Autodesk Fusion 360 part; units mm, degrees
(part 3 of 3)
sketch "스케치4" plane through (0, 0, 0) normal (0, -1, 0) x (1, 0, 0)
  circle A0 centre (-215, 0) radius 2.05
  circle A1 centre (-155, -60) radius 2.05
  circle A2 centre (-155, 60) radius 2.05
  circle A3 centre (-95, 0) radius 2.05
  circle A4 centre (-155, 0) radius 2.05
  line L0 (-89.3831, 6.1447) -> (-93.6198, 5.748)
  arc A5 (-94.0551, 6.1063) -> (-93.6198, 5.748) centre (-93.6571, 6.1462) ccw
  arc A6 (-94.0551, 6.1063) -> (-95.151, 13.0255) centre (-155, 0) ccw
  arc A7 (-94.8478, 13.5009) -> (-95.151, 13.0255) centre (-94.7602, 13.1106) ccw
  line L1 (-94.8478, 13.5009) -> (-90.6958, 14.4328)
  spline S0 degree 3 poles (-87.963, 15.6993) (-89.4342, 14.8406) (-90.378, 14.5249) (-90.6958, 14.4328) knots 0 0 0 0 1 1 1 1
  spline S1 degree 3 poles (-81.0471, 21.4743) (-83.7822, 18.497) (-86.2119, 16.7247) (-87.963, 15.6993) knots 0 0 0 0 1 1 1 1
  arc A8 (-81.0471, 21.4743) -> (-82.5485, 26.0954) centre (-155, 0) ccw
  spline S2 degree 3 poles (-91.5382, 26.7024) (-89.5187, 26.9021) (-86.5113, 26.8963) (-82.5485, 26.0954) knots 0 0 0 0 1 1 1 1
  spline S3 degree 3 poles (-94.4934, 26.1207) (-94.1822, 26.2329) (-93.2331, 26.5323) (-91.5382, 26.7024) knots 0 0 0 0 1 1 1 1
  line L2 (-94.4934, 26.1207) -> (-98.4002, 24.4342)
  arc A9 (-98.925, 24.6405) -> (-98.4002, 24.4342) centre (-98.5588, 24.8014) ccw
  arc A10 (-98.925, 24.6405) -> (-102.1054, 30.8824) centre (-155, 0) ccw
  arc A11 (-101.9638, 31.4282) -> (-102.1054, 30.8824) centre (-101.7599, 31.084) ccw
  line L3 (-101.9638, 31.4282) -> (-98.303, 33.5975)
  spline S4 degree 3 poles (-96.0954, 35.6464) (-97.2292, 34.3752) (-98.0293, 33.7833) (-98.303, 33.5975) knots 0 0 0 0 1 1 1 1
  spline S5 degree 3 poles (-91.3025, 43.276) (-92.9838, 39.5992) (-94.7468, 37.1628) (-96.0954, 35.6464) knots 0 0 0 0 1 1 1 1
  arc A12 (-91.3025, 43.276) -> (-94.1585, 47.2069) centre (-155, 0) ccw
  spline S6 degree 3 poles (-102.8957, 45.0063) (-101.0368, 45.8202) (-98.1748, 46.7441) (-94.1585, 47.2069) knots 0 0 0 0 1 1 1 1
  spline S7 degree 3 poles (-105.5266, 43.5398) (-105.2653, 43.7427) (-104.4551, 44.3208) (-102.8957, 45.0063) knots 0 0 0 0 1 1 1 1
  line L4 (-105.5266, 43.5398) -> (-108.721, 40.7286)
  arc A13 (-109.2838, 40.7626) -> (-108.721, 40.7286) centre (-108.9852, 41.0288) ccw
  arc A14 (-109.2838, 40.7626) -> (-114.2374, 45.7162) centre (-155, 0) ccw
  arc A15 (-114.2714, 46.279) -> (-114.2374, 45.7162) centre (-113.9712, 46.0148) ccw
  line L5 (-114.2714, 46.279) -> (-111.4602, 49.4734)
  spline S8 degree 3 poles (-109.9937, 52.1043) (-110.6792, 50.5449) (-111.2573, 49.7347) (-111.4602, 49.4734) knots 0 0 0 0 1 1 1 1
  spline S9 degree 3 poles (-107.7931, 60.8415) (-108.2559, 56.8252) (-109.1798, 53.9632) (-109.9937, 52.1043) knots 0 0 0 0 1 1 1 1
  arc A16 (-107.7931, 60.8415) -> (-111.724, 63.6975) centre (-155, 0) ccw
  spline S10 degree 3 poles (-119.3536, 58.9046) (-117.8372, 60.2532) (-115.4008, 62.0162) (-111.724, 63.6975) knots 0 0 0 0 1 1 1 1
  spline S11 degree 3 poles (-121.4025, 56.697) (-121.2167, 56.9707) (-120.6248, 57.7708) (-119.3536, 58.9046) knots 0 0 0 0 1 1 1 1
  line L6 (-121.4025, 56.697) -> (-123.5718, 53.0362)
  arc A17 (-124.1176, 52.8946) -> (-123.5718, 53.0362) centre (-123.916, 53.2401) ccw
  arc A18 (-124.1176, 52.8946) -> (-130.3595, 56.075) centre (-155, 0) ccw
  arc A19 (-130.5658, 56.5998) -> (-130.3595, 56.075) centre (-130.1986, 56.4412) ccw
  line L7 (-130.5658, 56.5998) -> (-128.8793, 60.5066)
  spline S12 degree 3 poles (-128.2976, 63.4618) (-128.4677, 61.7669) (-128.7671, 60.8178) (-128.8793, 60.5066) knots 0 0 0 0 1 1 1 1
  spline S13 degree 3 poles (-128.9046, 72.4515) (-128.1037, 68.4887) (-128.0979, 65.4813) (-128.2976, 63.4618) knots 0 0 0 0 1 1 1 1
  arc A20 (-128.9046, 72.4515) -> (-133.5257, 73.9529) centre (-155, 0) ccw
  spline S14 degree 3 poles (-139.3007, 67.037) (-138.2753, 68.7881) (-136.503, 71.2178) (-133.5257, 73.9529) knots 0 0 0 0 1 1 1 1
  spline S15 degree 3 poles (-140.5672, 64.3042) (-140.4751, 64.622) (-140.1594, 65.5658) (-139.3007, 67.037) knots 0 0 0 0 1 1 1 1
  line L8 (-140.5672, 64.3042) -> (-141.4991, 60.1522)
  arc A21 (-141.9745, 59.849) -> (-141.4991, 60.1522) centre (-141.8894, 60.2398) ccw
  arc A22 (-141.9745, 59.849) -> (-148.8937, 60.9449) centre (-155, 0) ccw
  arc A23 (-149.252, 61.3802) -> (-148.8937, 60.9449) centre (-148.8538, 61.3429) ccw
  line L9 (-149.252, 61.3802) -> (-148.8553, 65.6169)
  spline S16 degree 3 poles (-149.2153, 68.6073) (-148.8533, 66.9428) (-148.8447, 65.9476) (-148.8553, 65.6169) knots 0 0 0 0 1 1 1 1
  spline S17 degree 3 poles (-152.5706, 76.9693) (-150.5842, 73.448) (-149.6495, 70.5896) (-149.2153, 68.6073) knots 0 0 0 0 1 1 1 1
  arc A24 (-152.5706, 76.9693) -> (-157.4294, 76.9693) centre (-155, 0) ccw
  spline S18 degree 3 poles (-160.7847, 68.6073) (-160.3505, 70.5896) (-159.4158, 73.448) (-157.4294, 76.9693) knots 0 0 0 0 1 1 1 1
  spline S19 degree 3 poles (-161.1447, 65.6169) (-161.1553, 65.9476) (-161.1467, 66.9428) (-160.7847, 68.6073) knots 0 0 0 0 1 1 1 1
  line L10 (-161.1447, 65.6169) -> (-160.748, 61.3802)
  arc A25 (-161.1063, 60.9449) -> (-160.748, 61.3802) centre (-161.1462, 61.3429) ccw
  arc A26 (-161.1063, 60.9449) -> (-168.0255, 59.849) centre (-155, 0) ccw
  arc A27 (-168.5009, 60.1522) -> (-168.0255, 59.849) centre (-168.1106, 60.2398) ccw
  line L11 (-168.5009, 60.1522) -> (-169.4328, 64.3042)
  spline S20 degree 3 poles (-170.6993, 67.037) (-169.8406, 65.5658) (-169.5249, 64.622) (-169.4328, 64.3042) knots 0 0 0 0 1 1 1 1
  spline S21 degree 3 poles (-176.4743, 73.9529) (-173.497, 71.2178) (-171.7247, 68.7881) (-170.6993, 67.037) knots 0 0 0 0 1 1 1 1
  arc A28 (-176.4743, 73.9529) -> (-181.0954, 72.4515) centre (-155, 0) ccw
  spline S22 degree 3 poles (-181.7024, 63.4618) (-181.9021, 65.4813) (-181.8963, 68.4887) (-181.0954, 72.4515) knots 0 0 0 0 1 1 1 1
  spline S23 degree 3 poles (-181.1207, 60.5066) (-181.2329, 60.8178) (-181.5323, 61.7669) (-181.7024, 63.4618) knots 0 0 0 0 1 1 1 1
  line L12 (-181.1207, 60.5066) -> (-179.4342, 56.5998)
  arc A29 (-179.6405, 56.075) -> (-179.4342, 56.5998) centre (-179.8014, 56.4412) ccw
  arc A30 (-179.6405, 56.075) -> (-185.8824, 52.8946) centre (-155, 0) ccw
  arc A31 (-186.4282, 53.0362) -> (-185.8824, 52.8946) centre (-186.084, 53.2401) ccw
  line L13 (-186.4282, 53.0362) -> (-188.5975, 56.697)
  spline S24 degree 3 poles (-190.6464, 58.9046) (-189.3752, 57.7708) (-188.7833, 56.9707) (-188.5975, 56.697) knots 0 0 0 0 1 1 1 1
  spline S25 degree 3 poles (-198.276, 63.6975) (-194.5992, 62.0162) (-192.1628, 60.2532) (-190.6464, 58.9046) knots 0 0 0 0 1 1 1 1
  arc A32 (-198.276, 63.6975) -> (-202.2069, 60.8415) centre (-155, 0) ccw
  spline S26 degree 3 poles (-200.0063, 52.1043) (-200.8202, 53.9632) (-201.7441, 56.8252) (-202.2069, 60.8415) knots 0 0 0 0 1 1 1 1
  spline S27 degree 3 poles (-198.5398, 49.4734) (-198.7427, 49.7347) (-199.3208, 50.5449) (-200.0063, 52.1043) knots 0 0 0 0 1 1 1 1
  line L14 (-198.5398, 49.4734) -> (-195.7286, 46.279)
  arc A33 (-195.7626, 45.7162) -> (-195.7286, 46.279) centre (-196.0288, 46.0148) ccw
  arc A34 (-195.7626, 45.7162) -> (-200.7162, 40.7626) centre (-155, 0) ccw
  arc A35 (-201.279, 40.7286) -> (-200.7162, 40.7626) centre (-201.0148, 41.0288) ccw
  line L15 (-201.279, 40.7286) -> (-204.4734, 43.5398)
  spline S28 degree 3 poles (-207.1043, 45.0063) (-205.5449, 44.3208) (-204.7347, 43.7427) (-204.4734, 43.5398) knots 0 0 0 0 1 1 1 1
  spline S29 degree 3 poles (-215.8415, 47.2069) (-211.8252, 46.7441) (-208.9632, 45.8202) (-207.1043, 45.0063) knots 0 0 0 0 1 1 1 1
  arc A36 (-215.8415, 47.2069) -> (-218.6975, 43.276) centre (-155, 0) ccw
  spline S30 degree 3 poles (-213.9046, 35.6464) (-215.2532, 37.1628) (-217.0162, 39.5992) (-218.6975, 43.276) knots 0 0 0 0 1 1 1 1
  spline S31 degree 3 poles (-211.697, 33.5975) (-211.9707, 33.7833) (-212.7708, 34.3752) (-213.9046, 35.6464) knots 0 0 0 0 1 1 1 1
  line L16 (-211.697, 33.5975) -> (-208.0362, 31.4282)
  arc A37 (-207.8946, 30.8824) -> (-208.0362, 31.4282) centre (-208.2401, 31.084) ccw
  arc A38 (-207.8946, 30.8824) -> (-211.075, 24.6405) centre (-155, 0) ccw
  arc A39 (-211.5998, 24.4342) -> (-211.075, 24.6405) centre (-211.4412, 24.8014) ccw
  line L17 (-211.5998, 24.4342) -> (-215.5066, 26.1207)
  spline S32 degree 3 poles (-218.4618, 26.7024) (-216.7669, 26.5323) (-215.8178, 26.2329) (-215.5066, 26.1207) knots 0 0 0 0 1 1 1 1
  spline S33 degree 3 poles (-227.4515, 26.0954) (-223.4887, 26.8963) (-220.4813, 26.9021) (-218.4618, 26.7024) knots 0 0 0 0 1 1 1 1
  arc A40 (-227.4515, 26.0954) -> (-228.9529, 21.4743) centre (-155, 0) ccw
  spline S34 degree 3 poles (-222.037, 15.6993) (-223.7881, 16.7247) (-226.2178, 18.497) (-228.9529, 21.4743) knots 0 0 0 0 1 1 1 1
  spline S35 degree 3 poles (-219.3042, 14.4328) (-219.622, 14.5249) (-220.5658, 14.8406) (-222.037, 15.6993) knots 0 0 0 0 1 1 1 1
  line L18 (-219.3042, 14.4328) -> (-215.1522, 13.5009)
  arc A41 (-214.849, 13.0255) -> (-215.1522, 13.5009) centre (-215.2398, 13.1106) ccw
  arc A42 (-214.849, 13.0255) -> (-215.9449, 6.1063) centre (-155, 0) ccw
  arc A43 (-216.3802, 5.748) -> (-215.9449, 6.1063) centre (-216.3429, 6.1462) ccw
  line L19 (-216.3802, 5.748) -> (-220.6169, 6.1447)
  spline S36 degree 3 poles (-223.6073, 5.7847) (-221.9428, 6.1467) (-220.9476, 6.1553) (-220.6169, 6.1447) knots 0 0 0 0 1 1 1 1
  spline S37 degree 3 poles (-231.9693, 2.4294) (-228.448, 4.4158) (-225.5896, 5.3505) (-223.6073, 5.7847) knots 0 0 0 0 1 1 1 1
  arc A44 (-231.9693, 2.4294) -> (-231.9693, -2.4294) centre (-155, 0) ccw
  spline S38 degree 3 poles (-223.6073, -5.7847) (-225.5896, -5.3505) (-228.448, -4.4158) (-231.9693, -2.4294) knots 0 0 0 0 1 1 1 1
  spline S39 degree 3 poles (-220.6169, -6.1447) (-220.9476, -6.1553) (-221.9428, -6.1467) (-223.6073, -5.7847) knots 0 0 0 0 1 1 1 1
  line L20 (-220.6169, -6.1447) -> (-216.3802, -5.748)
  arc A45 (-215.9449, -6.1063) -> (-216.3802, -5.748) centre (-216.3429, -6.1462) ccw
  arc A46 (-215.9449, -6.1063) -> (-214.849, -13.0255) centre (-155, 0) ccw
  arc A47 (-215.1522, -13.5009) -> (-214.849, -13.0255) centre (-215.2398, -13.1106) ccw
  line L21 (-215.1522, -13.5009) -> (-219.3042, -14.4328)
  spline S40 degree 3 poles (-222.037, -15.6993) (-220.5658, -14.8406) (-219.622, -14.5249) (-219.3042, -14.4328) knots 0 0 0 0 1 1 1 1
  spline S41 degree 3 poles (-228.9529, -21.4743) (-226.2178, -18.497) (-223.7881, -16.7247) (-222.037, -15.6993) knots 0 0 0 0 1 1 1 1
  arc A48 (-228.9529, -21.4743) -> (-227.4515, -26.0954) centre (-155, 0) ccw
  spline S42 degree 3 poles (-218.4618, -26.7024) (-220.4813, -26.9021) (-223.4887, -26.8963) (-227.4515, -26.0954) knots 0 0 0 0 1 1 1 1
  spline S43 degree 3 poles (-215.5066, -26.1207) (-215.8178, -26.2329) (-216.7669, -26.5323) (-218.4618, -26.7024) knots 0 0 0 0 1 1 1 1
  line L22 (-215.5066, -26.1207) -> (-211.5998, -24.4342)
  arc A49 (-211.075, -24.6405) -> (-211.5998, -24.4342) centre (-211.4412, -24.8014) ccw
  arc A50 (-211.075, -24.6405) -> (-207.8946, -30.8824) centre (-155, 0) ccw
  arc A51 (-208.0362, -31.4282) -> (-207.8946, -30.8824) centre (-208.2401, -31.084) ccw
  line L23 (-208.0362, -31.4282) -> (-211.697, -33.5975)
  spline S44 degree 3 poles (-213.9046, -35.6464) (-212.7708, -34.3752) (-211.9707, -33.7833) (-211.697, -33.5975) knots 0 0 0 0 1 1 1 1
  spline S45 degree 3 poles (-218.6975, -43.276) (-217.0162, -39.5992) (-215.2532, -37.1628) (-213.9046, -35.6464) knots 0 0 0 0 1 1 1 1
  arc A52 (-218.6975, -43.276) -> (-215.8415, -47.2069) centre (-155, 0) ccw
  spline S46 degree 3 poles (-207.1043, -45.0063) (-208.9632, -45.8202) (-211.8252, -46.7441) (-215.8415, -47.2069) knots 0 0 0 0 1 1 1 1
  spline S47 degree 3 poles (-204.4734, -43.5398) (-204.7347, -43.7427) (-205.5449, -44.3208) (-207.1043, -45.0063) knots 0 0 0 0 1 1 1 1
  line L24 (-204.4734, -43.5398) -> (-201.279, -40.7286)
  arc A53 (-200.7162, -40.7626) -> (-201.279, -40.7286) centre (-201.0148, -41.0288) ccw
  arc A54 (-200.7162, -40.7626) -> (-195.7626, -45.7162) centre (-155, 0) ccw
  arc A55 (-195.7286, -46.279) -> (-195.7626, -45.7162) centre (-196.0288, -46.0148) ccw
  line L25 (-195.7286, -46.279) -> (-198.5398, -49.4734)
  spline S48 degree 3 poles (-200.0063, -52.1043) (-199.3208, -50.5449) (-198.7427, -49.7347) (-198.5398, -49.4734) knots 0 0 0 0 1 1 1 1
  spline S49 degree 3 poles (-202.2069, -60.8415) (-201.7441, -56.8252) (-200.8202, -53.9632) (-200.0063, -52.1043) knots 0 0 0 0 1 1 1 1
  arc A56 (-202.2069, -60.8415) -> (-198.276, -63.6975) centre (-155, 0) ccw
  spline S50 degree 3 poles (-190.6464, -58.9046) (-192.1628, -60.2532) (-194.5992, -62.0162) (-198.276, -63.6975) knots 0 0 0 0 1 1 1 1
  spline S51 degree 3 poles (-188.5975, -56.697) (-188.7833, -56.9707) (-189.3752, -57.7708) (-190.6464, -58.9046) knots 0 0 0 0 1 1 1 1
  line L26 (-188.5975, -56.697) -> (-186.4282, -53.0362)
  arc A57 (-185.8824, -52.8946) -> (-186.4282, -53.0362) centre (-186.084, -53.2401) ccw
  arc A58 (-185.8824, -52.8946) -> (-179.6405, -56.075) centre (-155, 0) ccw
  arc A59 (-179.4342, -56.5998) -> (-179.6405, -56.075) centre (-179.8014, -56.4412) ccw
  line L27 (-179.4342, -56.5998) -> (-181.1207, -60.5066)
  spline S52 degree 3 poles (-181.7024, -63.4618) (-181.5323, -61.7669) (-181.2329, -60.8178) (-181.1207, -60.5066) knots 0 0 0 0 1 1 1 1
  spline S53 degree 3 poles (-181.0954, -72.4515) (-181.8963, -68.4887) (-181.9021, -65.4813) (-181.7024, -63.4618) knots 0 0 0 0 1 1 1 1
  arc A60 (-181.0954, -72.4515) -> (-176.4743, -73.9529) centre (-155, 0) ccw
  spline S54 degree 3 poles (-170.6993, -67.037) (-171.7247, -68.7881) (-173.497, -71.2178) (-176.4743, -73.9529) knots 0 0 0 0 1 1 1 1
  spline S55 degree 3 poles (-169.4328, -64.3042) (-169.5249, -64.622) (-169.8406, -65.5658) (-170.6993, -67.037) knots 0 0 0 0 1 1 1 1
  line L28 (-169.4328, -64.3042) -> (-168.5009, -60.1522)
  arc A61 (-168.0255, -59.849) -> (-168.5009, -60.1522) centre (-168.1106, -60.2398) ccw
  arc A62 (-168.0255, -59.849) -> (-161.1063, -60.9449) centre (-155, 0) ccw
  arc A63 (-160.748, -61.3802) -> (-161.1063, -60.9449) centre (-161.1462, -61.3429) ccw
  line L29 (-160.748, -61.3802) -> (-161.1447, -65.6169)
  spline S56 degree 3 poles (-160.7847, -68.6073) (-161.1467, -66.9428) (-161.1553, -65.9476) (-161.1447, -65.6169) knots 0 0 0 0 1 1 1 1
  spline S57 degree 3 poles (-157.4294, -76.9693) (-159.4158, -73.448) (-160.3505, -70.5896) (-160.7847, -68.6073) knots 0 0 0 0 1 1 1 1
  arc A64 (-157.4294, -76.9693) -> (-152.5706, -76.9693) centre (-155, 0) ccw
  spline S58 degree 3 poles (-149.2153, -68.6073) (-149.6495, -70.5896) (-150.5842, -73.448) (-152.5706, -76.9693) knots 0 0 0 0 1 1 1 1
  spline S59 degree 3 poles (-148.8553, -65.6169) (-148.8447, -65.9476) (-148.8533, -66.9428) (-149.2153, -68.6073) knots 0 0 0 0 1 1 1 1
  line L30 (-148.8553, -65.6169) -> (-149.252, -61.3802)
  arc A65 (-148.8937, -60.9449) -> (-149.252, -61.3802) centre (-148.8538, -61.3429) ccw
  arc A66 (-148.8937, -60.9449) -> (-141.9745, -59.849) centre (-155, 0) ccw
  arc A67 (-141.4991, -60.1522) -> (-141.9745, -59.849) centre (-141.8894, -60.2398) ccw
  line L31 (-141.4991, -60.1522) -> (-140.5672, -64.3042)
  spline S60 degree 3 poles (-139.3007, -67.037) (-140.1594, -65.5658) (-140.4751, -64.622) (-140.5672, -64.3042) knots 0 0 0 0 1 1 1 1
  spline S61 degree 3 poles (-133.5257, -73.9529) (-136.503, -71.2178) (-138.2753, -68.7881) (-139.3007, -67.037) knots 0 0 0 0 1 1 1 1
  arc A68 (-133.5257, -73.9529) -> (-128.9046, -72.4515) centre (-155, 0) ccw
  spline S62 degree 3 poles (-128.2976, -63.4618) (-128.0979, -65.4813) (-128.1037, -68.4887) (-128.9046, -72.4515) knots 0 0 0 0 1 1 1 1
  spline S63 degree 3 poles (-128.8793, -60.5066) (-128.7671, -60.8178) (-128.4677, -61.7669) (-128.2976, -63.4618) knots 0 0 0 0 1 1 1 1
  line L32 (-128.8793, -60.5066) -> (-130.5658, -56.5998)
  arc A69 (-130.3595, -56.075) -> (-130.5658, -56.5998) centre (-130.1986, -56.4412) ccw
  arc A70 (-130.3595, -56.075) -> (-124.1176, -52.8946) centre (-155, 0) ccw
  arc A71 (-123.5718, -53.0362) -> (-124.1176, -52.8946) centre (-123.916, -53.2401) ccw
  line L33 (-123.5718, -53.0362) -> (-121.4025, -56.697)
  spline S64 degree 3 poles (-119.3536, -58.9046) (-120.6248, -57.7708) (-121.2167, -56.9707) (-121.4025, -56.697) knots 0 0 0 0 1 1 1 1
  spline S65 degree 3 poles (-111.724, -63.6975) (-115.4008, -62.0162) (-117.8372, -60.2532) (-119.3536, -58.9046) knots 0 0 0 0 1 1 1 1
  arc A72 (-111.724, -63.6975) -> (-107.7931, -60.8415) centre (-155, 0) ccw
  spline S66 degree 3 poles (-109.9937, -52.1043) (-109.1798, -53.9632) (-108.2559, -56.8252) (-107.7931, -60.8415) knots 0 0 0 0 1 1 1 1
  spline S67 degree 3 poles (-111.4602, -49.4734) (-111.2573, -49.7347) (-110.6792, -50.5449) (-109.9937, -52.1043) knots 0 0 0 0 1 1 1 1
  line L34 (-111.4602, -49.4734) -> (-114.2714, -46.279)
  arc A73 (-114.2374, -45.7162) -> (-114.2714, -46.279) centre (-113.9712, -46.0148) ccw
  arc A74 (-114.2374, -45.7162) -> (-109.2838, -40.7626) centre (-155, 0) ccw
  arc A75 (-108.721, -40.7286) -> (-109.2838, -40.7626) centre (-108.9852, -41.0288) ccw
  line L35 (-108.721, -40.7286) -> (-105.5266, -43.5398)
  spline S68 degree 3 poles (-102.8957, -45.0063) (-104.4551, -44.3208) (-105.2653, -43.7427) (-105.5266, -43.5398) knots 0 0 0 0 1 1 1 1
  spline S69 degree 3 poles (-94.1585, -47.2069) (-98.1748, -46.7441) (-101.0368, -45.8202) (-102.8957, -45.0063) knots 0 0 0 0 1 1 1 1
  arc A76 (-94.1585, -47.2069) -> (-91.3025, -43.276) centre (-155, 0) ccw
  spline S70 degree 3 poles (-96.0954, -35.6464) (-94.7468, -37.1628) (-92.9838, -39.5992) (-91.3025, -43.276) knots 0 0 0 0 1 1 1 1
  spline S71 degree 3 poles (-98.303, -33.5975) (-98.0293, -33.7833) (-97.2292, -34.3752) (-96.0954, -35.6464) knots 0 0 0 0 1 1 1 1
  line L36 (-98.303, -33.5975) -> (-101.9638, -31.4282)
  arc A77 (-102.1054, -30.8824) -> (-101.9638, -31.4282) centre (-101.7599, -31.084) ccw
  arc A78 (-102.1054, -30.8824) -> (-98.925, -24.6405) centre (-155, 0) ccw
  arc A79 (-98.4002, -24.4342) -> (-98.925, -24.6405) centre (-98.5588, -24.8014) ccw
  line L37 (-98.4002, -24.4342) -> (-94.4934, -26.1207)
  spline S72 degree 3 poles (-91.5382, -26.7024) (-93.2331, -26.5323) (-94.1822, -26.2329) (-94.4934, -26.1207) knots 0 0 0 0 1 1 1 1
  spline S73 degree 3 poles (-82.5485, -26.0954) (-86.5113, -26.8963) (-89.5187, -26.9021) (-91.5382, -26.7024) knots 0 0 0 0 1 1 1 1
  arc A80 (-82.5485, -26.0954) -> (-81.0471, -21.4743) centre (-155, 0) ccw
  spline S74 degree 3 poles (-87.963, -15.6993) (-86.2119, -16.7247) (-83.7822, -18.497) (-81.0471, -21.4743) knots 0 0 0 0 1 1 1 1
  spline S75 degree 3 poles (-90.6958, -14.4328) (-90.378, -14.5249) (-89.4342, -14.8406) (-87.963, -15.6993) knots 0 0 0 0 1 1 1 1
  line L38 (-90.6958, -14.4328) -> (-94.8478, -13.5009)
  arc A81 (-95.151, -13.0255) -> (-94.8478, -13.5009) centre (-94.7602, -13.1106) ccw
  arc A82 (-95.151, -13.0255) -> (-94.0551, -6.1063) centre (-155, 0) ccw
  arc A83 (-93.6198, -5.748) -> (-94.0551, -6.1063) centre (-93.6571, -6.1462) ccw
  line L39 (-93.6198, -5.748) -> (-89.3831, -6.1447)
  spline S76 degree 3 poles (-86.3927, -5.7847) (-88.0572, -6.1467) (-89.0524, -6.1553) (-89.3831, -6.1447) knots 0 0 0 0 1 1 1 1
  spline S77 degree 3 poles (-78.0307, -2.4294) (-81.552, -4.4158) (-84.4104, -5.3505) (-86.3927, -5.7847) knots 0 0 0 0 1 1 1 1
  arc A84 (-78.0307, -2.4294) -> (-78.0307, 2.4294) centre (-155, 0) ccw
  spline S78 degree 3 poles (-86.3927, 5.7847) (-84.4104, 5.3505) (-81.552, 4.4158) (-78.0307, 2.4294) knots 0 0 0 0 1 1 1 1
  spline S79 degree 3 poles (-89.3831, 6.1447) (-89.0524, 6.1553) (-88.0572, 6.1467) (-86.3927, 5.7847) knots 0 0 0 0 1 1 1 1
  circle A85 centre (-142.6, -0.2652) radius 2.05
  circle A86 centre (-154.7348, 12.4) radius 2.05
  circle A87 centre (-167.4, 0.2652) radius 2.05
  circle A88 centre (-155.2652, -12.4) radius 2.05
  circle A89 centre (-146.0444, 8.5806) radius 2.05
  circle A90 centre (-154.7348, 12.4) radius 2.05
  circle A91 centre (-163.5806, 8.9556) radius 2.05
  circle A92 centre (-167.4, 0.2652) radius 2.05
  circle A93 centre (-163.9556, -8.5806) radius 2.05
  circle A94 centre (-155.2652, -12.4) radius 2.05
  circle A95 centre (-146.4194, -8.9556) radius 2.05
  dimension "d21" = 4.1
  dimension "d22" = 12.4
  dimension "d24" = 360
  dimension "d28" = 360
  measures "d21" diameter of A85
  measures "d22" horizontal distance of A4.centre A85.centre
extrude "돌출3" cut sketch "스케치4" against normal blind 5 contours A85 | A86 A90 | A87 A92 | A88 A94 sketch seen with x (1, 0, 0) y (0, 1, 0) z (0, 0, 1) at (155, 0, 0) bodies 2 in component "Spur Gear (20 teeth) (1)"
extrude "돌출4" cut sketch "스케치4" against normal blind 5 contours A89 | A91 | A93 | A95 sketch seen with x (1, 0, 0) y (0, 1, 0) z (0, 0, 1) at (155, 0, 0) bodies 2 in component "Spur Gear (20 teeth) (1)"
component "Spur Gear (20 teeth)" placed x (1, 0, 0) y (0, 1, 0) z (0, 0, 1) at (0, 0, 0)
component "Spur Gear (20 teeth)" placed x (1, 0, 0) y (0, 1, 0) z (0, 0, 1) at (0, -4.5, 0)
component "Spur Gear (20 teeth) (1)" placed x (1, 0, 0) y (0, 1, 0) z (0, 0, 1) at (0, -9, 0)
component "Spur Gear (20 teeth) (1)" placed x (1, 0, 0) y (0, 1, 0) z (0, 0, 1) at (0, 4.5, 0)
